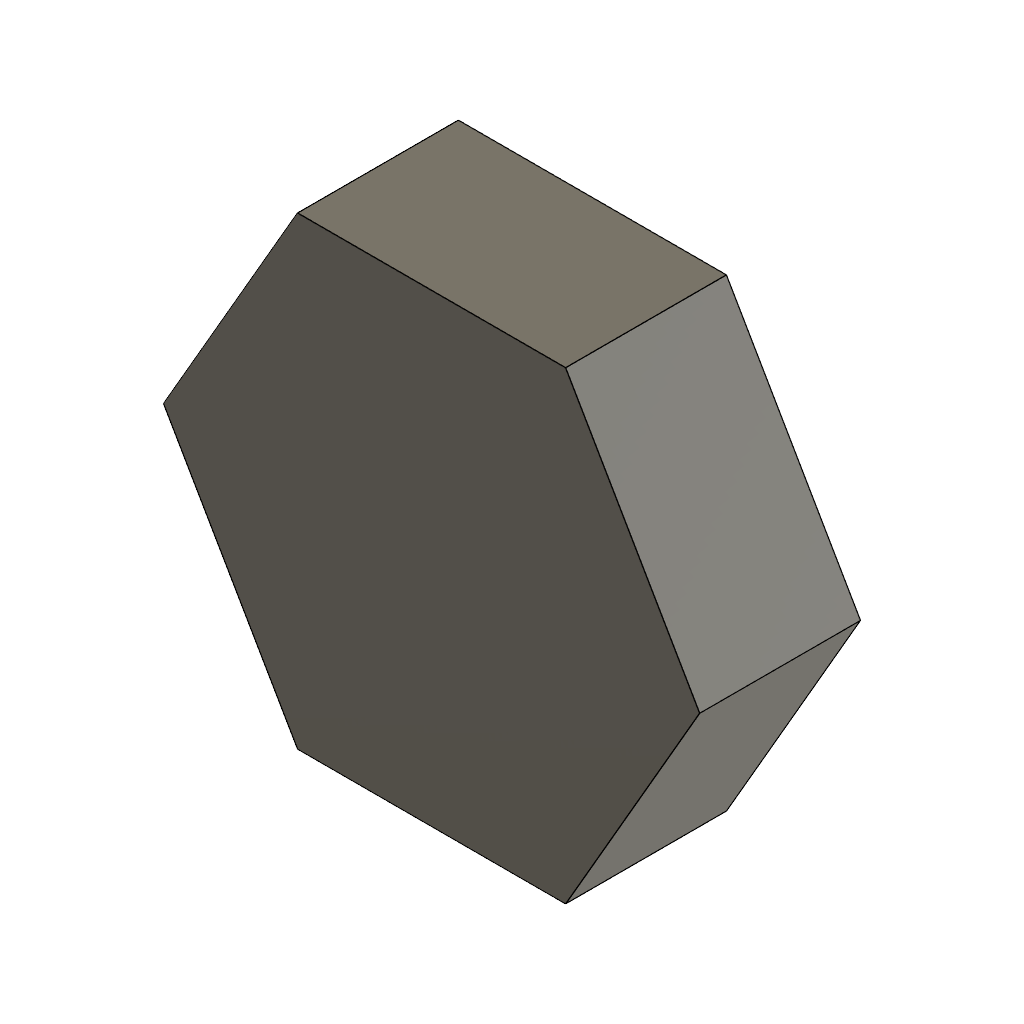
sk_polygon_hexagon (Autodesk Fusion 360 design; units mm, degrees)
part number: 2026-11-13-14-34-58-384
Autodesk Fusion 360 part; units mm, degrees
sketch "Sketch1" plane through (0, 0, 0) normal (0, 0, 1) x (1, 0, 0)
  line L0 (10, 0) -> (5, 8.6603)
  line L1 (5, 8.6603) -> (-5, 8.6603)
  line L2 (-5, 8.6603) -> (-10, 0)
  line L3 (-10, 0) -> (-5, -8.6603)
  line L4 (-5, -8.6603) -> (5, -8.6603)
  line L5 (5, -8.6603) -> (10, 0)
extrude "Extrude1" add sketch "Sketch1" along normal blind 6
